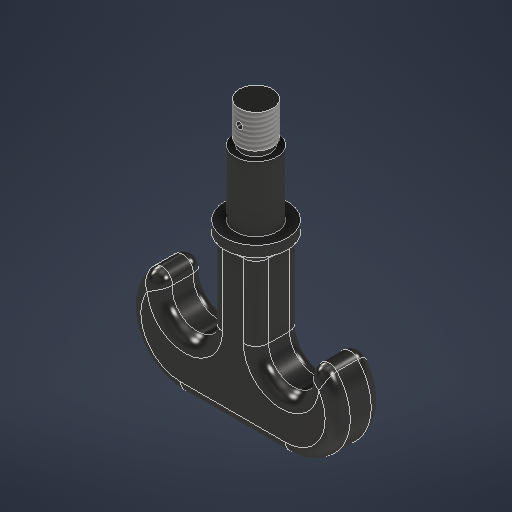
# Autodesk Inventor part: 1.Crane Hook
Saved by Autodesk Inventor 2025.2 (Build 292293000, 293)
## iProperties
Created: 2025-05-06
Part Number: 1.Crane Hook
Material: Steel, Mild
Document SubType Name: Modeling
Designer: trysm
Density: 7.85 g/cm^3
Appearance: Semi-Polished
Author: trysm
Autodesk Inventor part; units mm, degrees
ref_plane "YZ Plane" through (0, 0, 0) normal (1, 0, 0) x (0, 1, 0)
ref_plane "XZ Plane" through (0, 0, 0) normal (0, 1, 0) x (-1, 0, 0)
ref_plane "XY Plane" through (0, 0, 0) normal (0, 0, 1) x (1, 0, 0)
sketch "Sketch1" plane through (0, 0, 0) normal (0, 1, 0) x (-1, 0, 0)
  line L0 (0, 55) -> (8, 55)
  line L1 (8, 55) -> (8, 39)
  line L2 (8, 39) -> (7, 39)
  line L3 (7, 39) -> (7, 36)
  line L4 (7, 36) -> (10, 36)
  line L5 (10, 36) -> (10, 5)
  line L6 (10, 5) -> (15, 5)
  line L7 (15, 5) -> (15, 0)
  line L8 (15, 0) -> (0, 0)
  line L9 (0, 0) -> (0, 55)
  arc A0 (25, -75) -> (43.670592, -33.374448) centre (25, -50) ccw
  line L10 (25, -75) -> (0, -75)
  arc A1 (43.670592, -33.374448) -> (34.955158, -37.131406) centre (39.936474, -36.699558) ccw
  line L11 (11, 0) -> (11, -38.16784)
  arc A2 (11, -38.16784) -> (34.955158, -37.131406) centre (23, -38.16784) ccw
  line L12 (-11, 0) -> (0, 0)
  arc A3 (-43.670592, -33.374448) -> (-25, -75) centre (-25, -50) ccw
  line L13 (-25, -75) -> (0, -75)
  arc A4 (-34.955158, -37.131406) -> (-43.670592, -33.374448) centre (-39.936474, -36.699558) ccw
  line L14 (-11, 0) -> (-11, -38.16784)
  arc A5 (-34.955158, -37.131406) -> (-11, -38.16784) centre (-23, -38.16784) ccw
  circle A6 centre (0, 48) radius 1.5
  point P0 (-15, 0)
  dimension "d0" = 8
  dimension "d1" = 55
  dimension "d2" = 7
  dimension "d3" = 16
  dimension "d4" = 3
  dimension "d5" = 31
  dimension "d6" = 10
  dimension "d7" = 15
  dimension "d8" = 5
  dimension "d10" = 50
  dimension "d12" = 130
  dimension "d13" = 25
  dimension "d14" = 10
  dimension "d15" = 11
  dimension "d16" = 24
  dimension "d22" = 3
  dimension "d23" = 7
  constraints: 30 end point, 14 point on circle, 9 symmetric about line, 8 perpendicular, 7 centre point, 4 tangent, 3 point on line, 2 horizontal, 1 coincident, 1 vertical, 3 other
  measures "d0" distance of L0.start L0.end
  measures "d1" distance of L8.end L0.start
  measures "d2" distance between parallel lines of L9 L3
  measures "d3" distance of L0.end L1.end
  measures "d4" distance of L3.end L2.end
  measures "d5" distance of L4.end L5.end
  measures "d6" distance between parallel lines of L9 L5
  measures "d7" distance between parallel lines of L9 L7
  measures "d8" distance between parallel lines of L8 L6
  measures "d10" diameter of A0
  measures "d12" distance between parallel lines of L0 L10
  measures "d13" horizontal distance of point (0, 0) A0.centre
  measures "d14" diameter of A1
  measures "d15" distance from line of point (0, 0) L11
  measures "d16" diameter of A2
  measures "d22" diameter of A6
  measures "d23" distance from line of L0 A6.centre
revolve "Revolution1" add sketch "Sketch1" angle 360 about axis through (0, 0, 0) along (0, 0, 1) picked at (0.11126, 48.487464) contours L0 L1 L2 L3 L4 L5 L6 L7 L8 L9 A6 | A6 L9
extrude "Extrusion1" add sketch "Sketch1" along normal mid plane 22 contours L8 L11 A2 A1 A0 L10 L13 A3 A4 A5 L14 L12
fillet "Fillet1" radius 6 18 edges at (0, -11, -75) (47.8105, -11, -60.2314) (37.9572, -11, -32.108) (23.5187, -11, -50.1566) (11, -11, -19.0839) (-37.9572, -11, -32.108) (-23.5187, -11, -50.1566) (-11, -11, -19.0839) (-47.8105, -11, -60.2314) (-37.9572, 11, -32.108) (-23.5187, 11, -50.1566) (-11, 11, -19.0839) (0, 11, -75) (47.8105, 11, -60.2314) (37.9572, 11, -32.108) (23.5187, 11, -50.1566) (11, 11, -19.0839) (-47.8105, 11, -60.2314)
thread "Thread1" size "M16x2" class "6g" standard "ANSI Metric M Profile" full length
extrude "Extrusion2" cut sketch "Sketch1" along normal through all both and the other way through all contours A6 L9 | L9 A6
fillet "Fillet2" radius 3 8 edges at (0, -11, 0) (9.2426, -9.2426, 0) (11, 0, 0) (9.2426, 9.2426, 0) (0, 11, 0) (-9.2426, 9.2426, 0) (-11, 0, 0) (-9.2426, -9.2426, 0)
body "Solid1"
